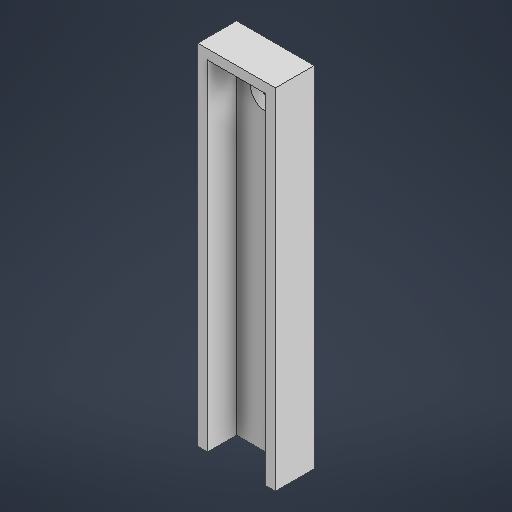
# Autodesk Inventor part: Camera_mount_front
Saved by Autodesk Inventor 2026.3 (Build 303398000, 398)
## iProperties
Created: 2026-09-23
Part Number: Camera_mount_front
Material: Generic
Document SubType Name: Modeling
Designer: grady
Density: 1 g/cm^3
Appearance: Default
Author: grady
Autodesk Inventor part; units mm, degrees
ref_plane "YZ Plane" through (0, 0, 0) normal (1, 0, 0) x (0, 1, 0)
ref_plane "XZ Plane" through (0, 0, 0) normal (0, 1, 0) x (-1, 0, 0)
ref_plane "XY Plane" through (0, 0, 0) normal (0, 0, 1) x (1, 0, 0)
sketch "Sketch1" plane through (0, 0, 0) normal (0, 0, 1) x (1, 0, 0)
  line L0 (0, 0) -> (40, 0)
  line L1 (40, 0) -> (40, 180)
  line L2 (40, 180) -> (0, 180)
  line L3 (0, 180) -> (0, 0)
  dimension "d0" = 40
  dimension "d1" = 180
  constraints: 8 end point, 2 parallel, 1 horizontal, 1 perpendicular
  measures "d0" distance of L2.end L1.end
  measures "d1" distance of L1.end L0.end
extrude "Extrusion1" add sketch "Sketch1" along normal blind 20
sketch "Sketch2" plane through (0, 0, 20) normal (0, 0, 1) x (1, 0, 0)
  line L0 (0, 0) -> (40, 0) projected
  line L1 (0, 0) -> (5, 0)
  line L2 (40, 0) -> (35, 0)
  line L3 (5, 0) -> (40, 0)
  line L4 (5, 0) -> (34, 0)
  line L5 (5, 0) -> (35, 0)
  line L6 (35, 0) -> (35, 175)
  line L7 (35, 175) -> (5, 175)
  line L8 (5, 175) -> (5, 0)
  dimension "d4" = 5
  dimension "d5" = 5
  dimension "d14" = 175
  constraints: 16 end point, 3 horizontal, 2 parallel, 2 point on line, 1 perpendicular
  measures "d4" distance of L0.start L1.end
  measures "d5" distance of L0.end L2.end
  measures "d14" distance of L6.end L5.end
extrude "Extrusion2" cut sketch "Sketch2" against normal blind 15
sketch "Sketch4" plane through (0, 0, 5) normal (0, 0, 1) x (1, 0, 0)
  line L0 (5, 175) -> (35, 175) projected
  line L1 (20, 175) -> (20, 160)
  circle A0 centre (20, 160) radius 8
  point P0 (0, 0)
  dimension "d19" = 15
  dimension "d20" = 16
  constraints: 2 end point, 1 centre point, 1 coincident, 1 midpoint, 1 vertical
  measures "d19" distance of L1.start L1.end
  measures "d20" diameter of A0
extrude "Extrusion5" cut sketch "Sketch4" against normal blind 5
body "Solid1"
